Autodesk Inventor part; units mm, degrees
(part 3 of 3)
sketch "Sketch15" plane through (0, 7, 0) normal (0, 1, 0) x (1, 0, 0)
  line L0 (95, 122.5) -> (95, 116.5) projected
  line L1 (95, 116.5) -> (92, 116.5) projected
  line L2 (92, 116.5) -> (92, 122.5) projected
  line L3 (92, 122.5) -> (95, 122.5) projected
  line L4 (146.2845, 46) -> (146.2845, 49) projected
  line L5 (146.2845, 49) -> (156.2155, 49) projected
  line L6 (156.2155, 49) -> (156.2155, 46) projected
  line L7 (156.2155, 46) -> (146.2845, 46) projected
  line L8 (100, 124) -> (107.5, 124) projected
  line L9 (107.5, 124) -> (107.5, 121) projected
  line L10 (107.5, 121) -> (100, 121) projected
  line L11 (100, 121) -> (100, 124) projected
  line L12 (95, 53.5) -> (95, 47.5) projected
  line L13 (95, 47.5) -> (92, 47.5) projected
  line L14 (92, 47.5) -> (92, 53.5) projected
  line L15 (92, 53.5) -> (95, 53.5) projected
  line L16 (98.7845, 46) -> (98.7845, 49) projected
  line L17 (98.7845, 49) -> (108.7155, 49) projected
  line L18 (108.7155, 49) -> (108.7155, 46) projected
  line L19 (108.7155, 46) -> (98.7845, 46) projected
  line L20 (155, 121) -> (147.5, 121) projected
  line L21 (147.5, 121) -> (147.5, 124) projected
  line L22 (147.5, 124) -> (155, 124) projected
  line L23 (155, 124) -> (155, 121) projected
  circle A0 centre (265, 165) radius 1.8 projected
  circle A1 centre (245, 165) radius 1.8 projected
  circle A2 centre (239, 32) radius 1.8 projected
  circle A3 centre (224, 32) radius 1.8 projected
  circle A4 centre (381, -156.5) radius 1.5 projected
  circle A5 centre (134.575, -192.5) radius 1.5 projected
  circle A6 centre (10.325, -226.5) radius 1.5 projected
  line L24 (-299.5, -198) -> (0.5, -198) projected
  arc A7 (0.5, -213) -> (0.5, -198) centre (0.5, -205.5) ccw projected
  line L25 (0.5, -213) -> (-299.5, -213) projected
  arc A8 (-299.5, -198) -> (-299.5, -213) centre (-299.5, -205.5) ccw projected
  circle A9 centre (-123.175, -236) radius 1.65 projected
  line L26 (-282.4, -241.875) -> (-278.4, -241.875) projected
  arc A10 (-278.4, -244.125) -> (-278.4, -241.875) centre (-278.4, -243) ccw projected
  line L27 (-278.4, -244.125) -> (-282.4, -244.125) projected
  arc A11 (-282.4, -241.875) -> (-282.4, -244.125) centre (-282.4, -243) ccw projected
  arc A12 (-157.3, -244.125) -> (-157.3, -241.875) centre (-157.3, -243) ccw projected
  line L28 (-157.3, -244.125) -> (-161.3, -244.125) projected
  arc A13 (-161.3, -241.875) -> (-161.3, -244.125) centre (-161.3, -243) ccw projected
  line L29 (-161.3, -241.875) -> (-157.3, -241.875) projected
  circle A14 centre (-86.175, -236) radius 1.65 projected
  circle A15 centre (-59.675, -226.5) radius 1.5 projected
  circle A16 centre (43.075, -192.5) radius 1.5 projected
  circle A17 centre (381, -212.5) radius 1.5 projected
  circle A18 centre (311, -212.5) radius 1.5 projected
  line L30 (224.5, -222.5) -> (224.5, -252.5) projected
  arc A19 (184.5, -252.5) -> (224.5, -252.5) centre (204.5, -252.5) ccw projected
  line L31 (184.5, -252.5) -> (184.5, -222.5) projected
  arc A20 (224.5, -222.5) -> (184.5, -222.5) centre (204.5, -222.5) ccw projected
  circle A21 centre (134.575, -282.5) radius 1.5 projected
  circle A22 centre (10.325, -282.5) radius 1.5 projected
  circle A23 centre (-123.175, -273) radius 1.65 projected
  line L32 (-373.5, -240.25) -> (-369.5, -240.25) projected
  arc A24 (-369.5, -245.75) -> (-369.5, -240.25) centre (-369.5, -243) ccw projected
  line L33 (-369.5, -245.75) -> (-373.5, -245.75) projected
  arc A25 (-373.5, -240.25) -> (-373.5, -245.75) centre (-373.5, -243) ccw projected
  arc A26 (-252.4, -241.875) -> (-252.4, -244.125) centre (-252.4, -243) ccw projected
  line L34 (-252.4, -241.875) -> (-248.4, -241.875) projected
  arc A27 (-248.4, -244.125) -> (-248.4, -241.875) centre (-248.4, -243) ccw projected
  line L35 (-248.4, -244.125) -> (-252.4, -244.125) projected
  circle A28 centre (-86.175, -273) radius 1.65 projected
  circle A29 centre (-59.675, -282.5) radius 1.5 projected
  circle A30 centre (43.075, -282.5) radius 1.5 projected
  line L36 (332.5, -232) -> (362.5, -232) projected
  arc A31 (362.5, -262) -> (362.5, -232) centre (362.5, -247) ccw projected
  line L37 (362.5, -262) -> (332.5, -262) projected
  arc A32 (332.5, -232) -> (332.5, -262) centre (332.5, -247) ccw projected
  circle A33 centre (311, -156.5) radius 1.5 projected
  circle A34 centre (185.5, -321.5) radius 1 projected
  circle A35 centre (185.5, -79.5) radius 1 projected
  circle A36 centre (0, 184.5) radius 1 projected
  circle A37 centre (-335.5, 184.5) radius 1 projected
  circle A38 centre (-185.5, 321.5) radius 1 projected
  circle A39 centre (-424, -80) radius 1 projected
  circle A40 centre (-424, 80) radius 1 projected
  circle A41 centre (0, 321.5) radius 1 projected
  circle A42 centre (-185.5, 184.5) radius 1 projected
  circle A43 centre (-185.5, -79.5) radius 1 projected
  circle A44 centre (0, -79.5) radius 1 projected
  circle A45 centre (-185.5, -321.5) radius 1 projected
  circle A46 centre (335.5, -321.5) radius 1 projected
  circle A47 centre (335.5, -79.5) radius 1 projected
  circle A48 centre (185.5, 184.5) radius 1 projected
  circle A49 centre (335.5, 321.5) radius 1 projected
  circle A50 centre (-335.5, 321.5) radius 1 projected
  circle A51 centre (-424, -240) radius 1 projected
  circle A52 centre (-424, 240) radius 1 projected
  circle A53 centre (185.5, 321.5) radius 1 projected
  circle A54 centre (335.5, 184.5) radius 1 projected
  circle A55 centre (-335.5, -79.5) radius 1 projected
  circle A56 centre (0, -321.5) radius 1 projected
  circle A57 centre (-335.5, -321.5) radius 1 projected
  arc A58 (-442.5, -333) -> (-435.5, -340) centre (-435.5, -333) ccw projected
  line L38 (-435.5, -340) -> (-383.5, -340) projected
  line L39 (-383.5, -340) -> (-383.5, -333) projected
  line L40 (-383.5, -333) -> (-324.5, -333) projected
  line L41 (-324.5, -333) -> (-324.5, -340) projected
  line L42 (-324.5, -340) -> (-265.5, -340) projected
  line L43 (-265.5, -340) -> (-265.5, -333) projected
  line L44 (-265.5, -333) -> (-206.5, -333) projected
  line L45 (-206.5, -333) -> (-206.5, -340) projected
  line L46 (-206.5, -340) -> (-147.5, -340) projected
  line L47 (-147.5, -340) -> (-147.5, -333) projected
  line L48 (-147.5, -333) -> (-88.5, -333) projected
  line L49 (-88.5, -333) -> (-88.5, -340) projected
  line L50 (-88.5, -340) -> (-29.5, -340) projected
  line L51 (-29.5, -340) -> (-29.5, -333) projected
  line L52 (-29.5, -333) -> (29.5, -333) projected
  line L53 (29.5, -333) -> (29.5, -340) projected
  line L54 (29.5, -340) -> (88.5, -340) projected
  line L55 (88.5, -340) -> (88.5, -333) projected
  line L56 (88.5, -333) -> (147.5, -333) projected
  line L57 (147.5, -333) -> (147.5, -340) projected
  line L58 (147.5, -340) -> (206.5, -340) projected
  line L59 (206.5, -340) -> (206.5, -333) projected
  line L60 (206.5, -333) -> (265.5, -333) projected
  line L61 (265.5, -333) -> (265.5, -340) projected
  line L62 (265.5, -340) -> (324.5, -340) projected
  line L63 (324.5, -340) -> (324.5, -333) projected
  line L64 (324.5, -333) -> (383.5, -333) projected
  line L65 (383.5, -333) -> (383.5, -340) projected
  line L66 (383.5, -340) -> (435.5, -340) projected
  arc A59 (435.5, -340) -> (442.5, -333) centre (435.5, -333) ccw projected
  line L67 (442.5, -333) -> (442.5, -300) projected
  line L68 (442.5, -300) -> (435.5, -300) projected
  line L69 (435.5, -300) -> (435.5, -260) projected
  line L70 (435.5, -260) -> (442.5, -260) projected
  line L71 (442.5, -260) -> (442.5, -220) projected
  line L72 (442.5, -220) -> (435.5, -220) projected
  line L73 (435.5, -220) -> (435.5, -180) projected
  line L74 (435.5, -180) -> (442.5, -180) projected
  line L75 (442.5, -180) -> (442.5, -140) projected
  line L76 (442.5, -140) -> (435.5, -140) projected
  line L77 (435.5, -140) -> (435.5, -100) projected
  line L78 (435.5, -100) -> (442.5, -100) projected
  line L79 (442.5, -100) -> (442.5, -60) projected
  line L80 (442.5, -60) -> (435.5, -60) projected
  line L81 (435.5, -60) -> (435.5, -20) projected
  line L82 (435.5, -20) -> (442.5, -20) projected
  line L83 (442.5, -20) -> (442.5, 20) projected
  line L84 (442.5, 20) -> (435.5, 20) projected
  line L85 (435.5, 20) -> (435.5, 60) projected
  line L86 (435.5, 60) -> (442.5, 60) projected
  line L87 (442.5, 60) -> (442.5, 100) projected
  line L88 (442.5, 100) -> (435.5, 100) projected
  line L89 (435.5, 100) -> (435.5, 140) projected
  line L90 (435.5, 140) -> (442.5, 140) projected
  line L91 (442.5, 140) -> (442.5, 180) projected
  line L92 (442.5, 180) -> (435.5, 180) projected
  line L93 (435.5, 180) -> (435.5, 220) projected
  line L94 (435.5, 220) -> (442.5, 220) projected
  line L95 (442.5, 220) -> (442.5, 260) projected
  line L96 (442.5, 260) -> (435.5, 260) projected
  line L97 (435.5, 260) -> (435.5, 300) projected
  line L98 (435.5, 300) -> (442.5, 300) projected
  line L99 (442.5, 300) -> (442.5, 333) projected
  arc A60 (442.5, 333) -> (435.5, 340) centre (435.5, 333) ccw projected
  line L100 (435.5, 340) -> (383.5, 340) projected
  line L101 (383.5, 340) -> (383.5, 333) projected
  line L102 (383.5, 333) -> (324.5, 333) projected
  line L103 (324.5, 333) -> (324.5, 340) projected
  line L104 (324.5, 340) -> (265.5, 340) projected
  line L105 (265.5, 340) -> (265.5, 333) projected
  line L106 (265.5, 333) -> (206.5, 333) projected
  line L107 (206.5, 333) -> (206.5, 340) projected
  line L108 (206.5, 340) -> (147.5, 340) projected
  line L109 (147.5, 340) -> (147.5, 333) projected
  line L110 (147.5, 333) -> (88.5, 333) projected
  line L111 (88.5, 333) -> (88.5, 340) projected
  line L112 (88.5, 340) -> (29.5, 340) projected
  line L113 (29.5, 340) -> (29.5, 333) projected
  line L114 (29.5, 333) -> (-29.5, 333) projected
  line L115 (-29.5, 333) -> (-29.5, 340) projected
  line L116 (-29.5, 340) -> (-88.5, 340) projected
  line L117 (-88.5, 340) -> (-88.5, 333) projected
  line L118 (-88.5, 333) -> (-147.5, 333) projected
  line L119 (-147.5, 333) -> (-147.5, 340) projected
  line L120 (-147.5, 340) -> (-206.5, 340) projected
  line L121 (-206.5, 340) -> (-206.5, 333) projected
  line L122 (-206.5, 333) -> (-265.5, 333) projected
  line L123 (-265.5, 333) -> (-265.5, 340) projected
  line L124 (-265.5, 340) -> (-324.5, 340) projected
  line L125 (-324.5, 340) -> (-324.5, 333) projected
  line L126 (-324.5, 333) -> (-383.5, 333) projected
  line L127 (-383.5, 333) -> (-383.5, 340) projected
  line L128 (-383.5, 340) -> (-435.5, 340) projected
  arc A61 (-435.5, 340) -> (-442.5, 333) centre (-435.5, 333) ccw projected
  line L129 (-442.5, 333) -> (-442.5, 300) projected
  line L130 (-442.5, 300) -> (-435.5, 300) projected
  line L131 (-435.5, 300) -> (-435.5, 260) projected
  line L132 (-435.5, 260) -> (-442.5, 260) projected
  line L133 (-442.5, 260) -> (-442.5, 220) projected
  line L134 (-442.5, 220) -> (-435.5, 220) projected
  line L135 (-435.5, 220) -> (-435.5, 180) projected
  line L136 (-435.5, 180) -> (-442.5, 180) projected
  line L137 (-442.5, 180) -> (-442.5, 140) projected
  line L138 (-442.5, 140) -> (-435.5, 140) projected
  line L139 (-435.5, 140) -> (-435.5, 100) projected
  line L140 (-435.5, 100) -> (-442.5, 100) projected
  line L141 (-442.5, 100) -> (-442.5, 60) projected
  line L142 (-442.5, 60) -> (-435.5, 60) projected
  line L143 (-435.5, 60) -> (-435.5, 20) projected
  line L144 (-435.5, 20) -> (-442.5, 20) projected
  line L145 (-442.5, 20) -> (-442.5, -20) projected
  line L146 (-442.5, -20) -> (-435.5, -20) projected
  line L147 (-435.5, -20) -> (-435.5, -60) projected
  line L148 (-435.5, -60) -> (-442.5, -60) projected
  line L149 (-442.5, -60) -> (-442.5, -100) projected
  line L150 (-442.5, -100) -> (-435.5, -100) projected
  line L151 (-435.5, -100) -> (-435.5, -140) projected
  line L152 (-435.5, -140) -> (-442.5, -140) projected
  line L153 (-442.5, -140) -> (-442.5, -180) projected
  line L154 (-442.5, -180) -> (-435.5, -180) projected
  line L155 (-435.5, -180) -> (-435.5, -220) projected
  line L156 (-435.5, -220) -> (-442.5, -220) projected
  line L157 (-442.5, -220) -> (-442.5, -260) projected
  line L158 (-442.5, -260) -> (-435.5, -260) projected
  line L159 (-435.5, -260) -> (-435.5, -300) projected
  line L160 (-435.5, -300) -> (-442.5, -300) projected
  line L161 (-442.5, -300) -> (-442.5, -333) projected
  line L162 (97.5, -297) -> (97.5, -300) projected
  line L163 (97.5, -300) -> (-242.5, -300) projected
  line L164 (-242.5, -300) -> (-242.5, -297) projected
  line L165 (-242.5, -297) -> (97.5, -297) projected
  arc A62 (-388, -282.9) -> (-388, -277.1) centre (-388, -280) ccw projected
  line L166 (-388, -282.9) -> (-391, -282.9) projected
  arc A63 (-391, -277.1) -> (-391, -282.9) centre (-391, -280) ccw projected
  line L167 (-391, -277.1) -> (-388, -277.1) projected
  line L168 (211.6, -288.5) -> (211.6, -285.5) projected
  arc A64 (217.4, -285.5) -> (211.6, -285.5) centre (214.5, -285.5) ccw projected
  line L169 (217.4, -285.5) -> (217.4, -288.5) projected
  arc A65 (211.6, -288.5) -> (217.4, -288.5) centre (214.5, -288.5) ccw projected
  line L170 (383, -259.1) -> (386, -259.1) projected
  arc A66 (386, -264.9) -> (386, -259.1) centre (386, -262) ccw projected
  line L171 (386, -264.9) -> (383, -264.9) projected
  arc A67 (383, -259.1) -> (383, -264.9) centre (383, -262) ccw projected
  line L172 (297.5, -150) -> (300.5, -150) projected
  line L173 (300.5, -150) -> (300.5, -250) projected
  line L174 (300.5, -250) -> (297.5, -250) projected
  line L175 (297.5, -250) -> (297.5, -150) projected
  arc A68 (376.6, -114.5) -> (382.4, -114.5) centre (379.5, -114.5) ccw projected
  line L176 (376.6, -114.5) -> (376.6, -111.5) projected
  arc A69 (382.4, -111.5) -> (376.6, -111.5) centre (379.5, -111.5) ccw projected
  line L177 (382.4, -111.5) -> (382.4, -114.5) projected
  line L178 (372.5, -100) -> (372.5, -103) projected
  line L179 (372.5, -103) -> (322.5, -103) projected
  line L180 (322.5, -103) -> (322.5, -100) projected
  line L181 (322.5, -100) -> (372.5, -100) projected
  line L182 (394.5, -150) -> (397.5, -150) projected
  line L183 (397.5, -150) -> (397.5, -250) projected
  line L184 (397.5, -250) -> (394.5, -250) projected
  line L185 (394.5, -250) -> (394.5, -150) projected
  line L186 (382.4, -285.5) -> (382.4, -288.5) projected
  arc A70 (376.6, -288.5) -> (382.4, -288.5) centre (379.5, -288.5) ccw projected
  line L187 (376.6, -288.5) -> (376.6, -285.5) projected
  arc A71 (382.4, -285.5) -> (376.6, -285.5) centre (379.5, -285.5) ccw projected
  arc A72 (211.6, -189.5) -> (217.4, -189.5) centre (214.5, -189.5) ccw projected
  line L188 (211.6, -189.5) -> (211.6, -186.5) projected
  arc A73 (217.4, -186.5) -> (211.6, -186.5) centre (214.5, -186.5) ccw projected
  line L189 (217.4, -186.5) -> (217.4, -189.5) projected
  arc A74 (-391, -192.1) -> (-391, -197.9) centre (-391, -195) ccw projected
  line L190 (-391, -192.1) -> (-388, -192.1) projected
  arc A75 (-388, -197.9) -> (-388, -192.1) centre (-388, -195) ccw projected
  line L191 (-388, -197.9) -> (-391, -197.9) projected
  line L192 (-242.5, -178) -> (-242.5, -175) projected
  line L193 (-242.5, -175) -> (97.5, -175) projected
  line L194 (97.5, -175) -> (97.5, -178) projected
  line L195 (97.5, -178) -> (-242.5, -178) projected
  line L196 (-399.5, -287.5) -> (-402.5, -287.5) projected
  line L197 (-402.5, -287.5) -> (-402.5, -187.5) projected
  line L198 (-402.5, -187.5) -> (-399.5, -187.5) projected
  line L199 (-399.5, -187.5) -> (-399.5, -287.5) projected
  arc A76 (-356.6, -285.5) -> (-362.4, -285.5) centre (-359.5, -285.5) ccw projected
  line L200 (-356.6, -285.5) -> (-356.6, -288.5) projected
  arc A77 (-362.4, -288.5) -> (-356.6, -288.5) centre (-359.5, -288.5) ccw projected
  line L201 (-362.4, -288.5) -> (-362.4, -285.5) projected
  line L202 (243, -277.1) -> (246, -277.1) projected
  arc A78 (246, -282.9) -> (246, -277.1) centre (246, -280) ccw projected
  line L203 (246, -282.9) -> (243, -282.9) projected
  arc A79 (243, -277.1) -> (243, -282.9) centre (243, -280) ccw projected
  arc A80 (318.4, -285.5) -> (312.6, -285.5) centre (315.5, -285.5) ccw projected
  line L204 (318.4, -285.5) -> (318.4, -288.5) projected
  arc A81 (312.6, -288.5) -> (318.4, -288.5) centre (315.5, -288.5) ccw projected
  line L205 (312.6, -288.5) -> (312.6, -285.5) projected
  line L206 (318.4, -111.5) -> (318.4, -114.5) projected
  arc A82 (312.6, -114.5) -> (318.4, -114.5) centre (315.5, -114.5) ccw projected
  line L207 (312.6, -114.5) -> (312.6, -111.5) projected
  arc A83 (318.4, -111.5) -> (312.6, -111.5) centre (315.5, -111.5) ccw projected
  arc A84 (386, -140.9) -> (386, -135.1) centre (386, -138) ccw projected
  line L208 (386, -140.9) -> (383, -140.9) projected
  arc A85 (383, -135.1) -> (383, -140.9) centre (383, -138) ccw projected
  line L209 (383, -135.1) -> (386, -135.1) projected
  line L210 (309, -135.1) -> (312, -135.1) projected
  arc A86 (312, -140.9) -> (312, -135.1) centre (312, -138) ccw projected
  line L211 (312, -140.9) -> (309, -140.9) projected
  arc A87 (309, -135.1) -> (309, -140.9) centre (309, -138) ccw projected
  arc A88 (309, -259.1) -> (309, -264.9) centre (309, -262) ccw projected
  line L212 (309, -259.1) -> (312, -259.1) projected
  arc A89 (312, -264.9) -> (312, -259.1) centre (312, -262) ccw projected
  line L213 (312, -264.9) -> (309, -264.9) projected
  line L214 (322.5, -300) -> (322.5, -297) projected
  line L215 (322.5, -297) -> (372.5, -297) projected
  line L216 (372.5, -297) -> (372.5, -300) projected
  line L217 (372.5, -300) -> (322.5, -300) projected
  arc A90 (246, -197.9) -> (246, -192.1) centre (246, -195) ccw projected
  line L218 (246, -197.9) -> (243, -197.9) projected
  arc A91 (243, -192.1) -> (243, -197.9) centre (243, -195) ccw projected
  line L219 (243, -192.1) -> (246, -192.1) projected
  line L220 (-362.4, -189.5) -> (-362.4, -186.5) projected
  arc A92 (-356.6, -186.5) -> (-362.4, -186.5) centre (-359.5, -186.5) ccw projected
  line L221 (-356.6, -186.5) -> (-356.6, -189.5) projected
  arc A93 (-362.4, -189.5) -> (-356.6, -189.5) centre (-359.5, -189.5) ccw projected
  line L222 (254.5, -187.5) -> (257.5, -187.5) projected
  line L223 (257.5, -187.5) -> (257.5, -287.5) projected
  line L224 (257.5, -287.5) -> (254.5, -287.5) projected
  line L225 (254.5, -287.5) -> (254.5, -187.5) projected
  line L226 (202.5, 101) -> (355.1, 101) projected
  arc A94 (358.1, 98) -> (355.1, 101) centre (355.1, 98) ccw projected
  line L227 (358.1, 98) -> (358.1, 72) projected
  arc A95 (355.1, 69) -> (358.1, 72) centre (355.1, 72) ccw projected
  line L228 (355.1, 69) -> (202.5, 69) projected
  arc A96 (199.5, 72) -> (202.5, 69) centre (202.5, 72) ccw projected
  line L229 (199.5, 72) -> (199.5, 98) projected
  arc A97 (202.5, 101) -> (199.5, 98) centre (202.5, 98) ccw projected
  circle A98 centre (375.1, 69) radius 2.9 projected
  circle A99 centre (375.1, 101) radius 2.9 projected
  circle A100 centre (182.5, 69) radius 2.9 projected
  circle A101 centre (182.5, 101) radius 2.9 projected
  arc A102 (200.9, 198.5) -> (195.1, 198.5) centre (198, 198.5) ccw projected
  line L230 (200.9, 198.5) -> (200.9, 195.5) projected
  arc A103 (195.1, 195.5) -> (200.9, 195.5) centre (198, 195.5) ccw projected
  line L231 (195.1, 195.5) -> (195.1, 198.5) projected
  line L232 (357, 193.5) -> (360, 193.5) projected
  line L233 (360, 193.5) -> (360, 173.5) projected
  line L234 (360, 173.5) -> (357, 173.5) projected
  line L235 (357, 173.5) -> (357, 193.5) projected
  line L236 (357, -3.5) -> (360, -3.5) projected
  line L237 (360, -3.5) -> (360, -23.5) projected
  line L238 (360, -23.5) -> (357, -23.5) projected
  line L239 (357, -23.5) -> (357, -3.5) projected
  line L240 (163, -23.5) -> (160, -23.5) projected
  line L241 (160, -23.5) -> (160, -3.5) projected
  line L242 (160, -3.5) -> (163, -3.5) projected
  line L243 (163, -3.5) -> (163, -23.5) projected
  arc A104 (345.5, -10.6) -> (345.5, -16.4) centre (345.5, -13.5) ccw projected
  line L244 (345.5, -10.6) -> (348.5, -10.6) projected
  arc A105 (348.5, -16.4) -> (348.5, -10.6) centre (348.5, -13.5) ccw projected
  line L245 (348.5, -16.4) -> (345.5, -16.4) projected
  line L246 (348.5, 180.6) -> (345.5, 180.6) projected
  arc A106 (345.5, 186.4) -> (345.5, 180.6) centre (345.5, 183.5) ccw projected
  line L247 (345.5, 186.4) -> (348.5, 186.4) projected
  arc A107 (348.5, 180.6) -> (348.5, 186.4) centre (348.5, 183.5) ccw projected
  arc A108 (174.5, 180.6) -> (174.5, 186.4) centre (174.5, 183.5) ccw projected
  line L248 (174.5, 180.6) -> (171.5, 180.6) projected
  arc A109 (171.5, 186.4) -> (171.5, 180.6) centre (171.5, 183.5) ccw projected
  line L249 (171.5, 186.4) -> (174.5, 186.4) projected
  line L250 (332.5, 210) -> (332.5, 207) projected
  line L251 (332.5, 207) -> (187.5, 207) projected
  line L252 (187.5, 207) -> (187.5, 210) projected
  line L253 (187.5, 210) -> (332.5, 210) projected
  arc A110 (324.9, -25.5) -> (319.1, -25.5) centre (322, -25.5) ccw projected
  line L254 (324.9, -25.5) -> (324.9, -28.5) projected
  arc A111 (319.1, -28.5) -> (324.9, -28.5) centre (322, -28.5) ccw projected
  line L255 (319.1, -28.5) -> (319.1, -25.5) projected
  line L256 (200.9, -25.5) -> (200.9, -28.5) projected
  arc A112 (195.1, -28.5) -> (200.9, -28.5) centre (198, -28.5) ccw projected
  line L257 (195.1, -28.5) -> (195.1, -25.5) projected
  arc A113 (200.9, -25.5) -> (195.1, -25.5) centre (198, -25.5) ccw projected
  line L258 (174.5, -16.4) -> (171.5, -16.4) projected
  arc A114 (171.5, -10.6) -> (171.5, -16.4) centre (171.5, -13.5) ccw projected
  line L259 (171.5, -10.6) -> (174.5, -10.6) projected
  arc A115 (174.5, -16.4) -> (174.5, -10.6) centre (174.5, -13.5) ccw projected
  line L260 (187.5, -40) -> (187.5, -37) projected
  line L261 (187.5, -37) -> (332.5, -37) projected
  line L262 (332.5, -37) -> (332.5, -40) projected
  line L263 (332.5, -40) -> (187.5, -40) projected
  line L264 (324.9, 198.5) -> (324.9, 195.5) projected
  arc A116 (319.1, 195.5) -> (324.9, 195.5) centre (322, 195.5) ccw projected
  line L265 (319.1, 195.5) -> (319.1, 198.5) projected
  arc A117 (324.9, 198.5) -> (319.1, 198.5) centre (322, 198.5) ccw projected
  line L266 (160, 193.5) -> (163, 193.5) projected
  line L267 (163, 193.5) -> (163, 173.5) projected
  line L268 (163, 173.5) -> (160, 173.5) projected
  line L269 (160, 173.5) -> (160, 193.5) projected
  line L270 (95.5, -49.5) -> (95.5, -34.5) projected
  line L271 (95.5, -34.5) -> (98.5, -34.5) projected
  line L272 (98.5, -34.5) -> (98.5, -49.5) projected
  line L273 (98.5, -49.5) -> (95.5, -49.5) projected
  arc A118 (135.5, -40) -> (140.5, -35) centre (135.5, -35) ccw projected
  line L274 (135.5, -40) -> (115.5, -40) projected
  arc A119 (110.5, -35) -> (115.5, -40) centre (115.5, -35) ccw projected
  line L275 (110.5, -35) -> (110.5, -25) projected
  arc A120 (115.5, -20) -> (110.5, -25) centre (115.5, -25) ccw projected
  line L276 (115.5, -20) -> (135.5, -20) projected
  arc A121 (140.5, -25) -> (135.5, -20) centre (135.5, -25) ccw projected
  line L277 (140.5, -25) -> (140.5, -35) projected
  line L278 (103.25, 40) -> (113.25, 40) projected
  line L279 (113.25, 40) -> (113.25, 37) projected
  line L280 (113.25, 37) -> (103.25, 37) projected
  line L281 (103.25, 37) -> (103.25, 40) projected
  line L282 (113, 130) -> (108, 130) projected
  line L283 (108, 130) -> (108, 133) projected
  line L284 (108, 133) -> (113, 133) projected
  line L285 (113, 133) -> (113, 130) projected
  line L286 (149, 130) -> (144, 130) projected
  line L287 (144, 130) -> (144, 133) projected
  line L288 (144, 133) -> (149, 133) projected
  line L289 (149, 133) -> (149, 130) projected
  circle A122 centre (132.41, 31.5) radius 1.25 projected
  line L290 (156.5, 138) -> (153.5, 138) projected
  line L291 (153.5, 138) -> (153.5, 148) projected
  line L292 (153.5, 148) -> (156.5, 148) projected
  line L293 (156.5, 148) -> (156.5, 138) projected
  line L294 (108, 156) -> (113, 156) projected
  line L295 (113, 156) -> (113, 153) projected
  line L296 (113, 153) -> (108, 153) projected
  line L297 (108, 153) -> (108, 156) projected
  line L298 (95.5, 14.5) -> (95.5, 29.5) projected
  line L299 (95.5, 29.5) -> (98.5, 29.5) projected
  line L300 (98.5, 29.5) -> (98.5, 14.5) projected
  line L301 (98.5, 14.5) -> (95.5, 14.5) projected
  line L302 (113.25, 4) -> (103.25, 4) projected
  line L303 (103.25, 4) -> (103.25, 7) projected
  line L304 (103.25, 7) -> (113.25, 7) projected
  line L305 (113.25, 7) -> (113.25, 4) projected
  line L306 (113.25, -60) -> (103.25, -60) projected
  line L307 (103.25, -60) -> (103.25, -57) projected
  line L308 (103.25, -57) -> (113.25, -57) projected
  line L309 (113.25, -57) -> (113.25, -60) projected
  line L310 (51.5, 95) -> (51.5, 75) projected
  line L311 (51.5, 75) -> (44.5, 75) projected
  line L312 (44.5, 75) -> (44.5, 95) projected
  line L313 (44.5, 95) -> (51.5, 95) projected
  line L314 (155.5, -34.5) -> (155.5, -49.5) projected
  line L315 (155.5, -49.5) -> (152.5, -49.5) projected
  line L316 (152.5, -49.5) -> (152.5, -34.5) projected
  line L317 (152.5, -34.5) -> (155.5, -34.5) projected
  line L318 (137.75, 40) -> (147.75, 40) projected
  line L319 (147.75, 40) -> (147.75, 37) projected
  line L320 (147.75, 37) -> (137.75, 37) projected
  line L321 (137.75, 37) -> (137.75, 40) projected
  line L322 (100.5, 138) -> (100.5, 148) projected
  line L323 (100.5, 148) -> (103.5, 148) projected
  line L324 (103.5, 148) -> (103.5, 138) projected
  line L325 (103.5, 138) -> (100.5, 138) projected
  line L326 (134.5, 139) -> (122.5, 139) projected
  arc A123 (122.5, 147) -> (122.5, 139) centre (122.5, 143) ccw projected
  line L327 (122.5, 147) -> (134.5, 147) projected
  arc A124 (134.5, 139) -> (134.5, 147) centre (134.5, 143) ccw projected
  circle A125 centre (118.59, 31.5) radius 1.25 projected
  line L328 (144, 156) -> (149, 156) projected
  line L329 (149, 156) -> (149, 153) projected
  line L330 (149, 153) -> (144, 153) projected
  line L331 (144, 153) -> (144, 156) projected
  line L332 (126.5, 136) -> (130.5, 136) projected
  line L333 (130.5, 136) -> (130.5, 133) projected
  line L334 (130.5, 133) -> (126.5, 133) projected
  line L335 (126.5, 133) -> (126.5, 136) projected
  line L336 (155.5, 29.5) -> (155.5, 14.5) projected
  line L337 (155.5, 14.5) -> (152.5, 14.5) projected
  line L338 (152.5, 14.5) -> (152.5, 29.5) projected
  line L339 (152.5, 29.5) -> (155.5, 29.5) projected
  line L340 (137.75, 4) -> (137.75, 7) projected
  line L341 (137.75, 7) -> (147.75, 7) projected
  line L342 (147.75, 7) -> (147.75, 4) projected
  line L343 (147.75, 4) -> (137.75, 4) projected
  line L344 (147.75, -60) -> (137.75, -60) projected
  line L345 (137.75, -60) -> (137.75, -57) projected
  line L346 (137.75, -57) -> (147.75, -57) projected
  line L347 (147.75, -57) -> (147.75, -60) projected
  line L348 (42.5, 92.5) -> (42.5, 77.5) projected
  line L349 (42.5, 77.5) -> (39.5, 77.5) projected
  line L350 (39.5, 77.5) -> (39.5, 92.5) projected
  line L351 (39.5, 92.5) -> (42.5, 92.5) projected
  circle A126 centre (32.5, 114.5) radius 2.75 projected
  circle A127 centre (32.5, 55.5) radius 2.75 projected
  circle A128 centre (-112.5, 155) radius 2.75 projected
  circle A129 centre (-47.5, 15) radius 2.75 projected
  circle A130 centre (-112.5, 15) radius 2.75 projected
  circle A131 centre (-47.5, 155) radius 2.75 projected
  circle A132 centre (-177.5, 155) radius 2.75 projected
  circle A133 centre (-177.5, 15) radius 2.75 projected
  line L352 (-407.5, 305) -> (-387.5, 305) projected
  line L353 (-387.5, 305) -> (-387.5, 285) projected
  line L354 (-387.5, 285) -> (-407.5, 285) projected
  line L355 (-407.5, 285) -> (-407.5, 305) projected
  arc A134 (-419, -122.1) -> (-419, -127.9) centre (-419, -125) ccw projected
  line L356 (-419, -122.1) -> (-416, -122.1) projected
  arc A135 (-416, -127.9) -> (-416, -122.1) centre (-416, -125) ccw projected
  line L357 (-416, -127.9) -> (-419, -127.9) projected
  arc A136 (100.4, -143.5) -> (94.6, -143.5) centre (97.5, -143.5) ccw projected
  line L358 (100.4, -143.5) -> (100.4, -146.5) projected
  arc A137 (94.6, -146.5) -> (100.4, -146.5) centre (97.5, -146.5) ccw projected
  line L359 (94.6, -146.5) -> (94.6, -143.5) projected
  line L360 (107.5, -115) -> (107.5, -135) projected
  line L361 (107.5, -135) -> (87.5, -135) projected
  line L362 (87.5, -135) -> (87.5, -115) projected
  line L363 (87.5, -115) -> (107.5, -115) projected
  arc A138 (100.4, 316.5) -> (94.6, 316.5) centre (97.5, 316.5) ccw projected
  line L364 (100.4, 316.5) -> (100.4, 313.5) projected
  arc A139 (94.6, 313.5) -> (100.4, 313.5) centre (97.5, 313.5) ccw projected
  line L365 (94.6, 313.5) -> (94.6, 316.5) projected
  arc A140 (76, 297.9) -> (76, 292.1) centre (76, 295) ccw projected
  line L366 (76, 297.9) -> (79, 297.9) projected
  arc A141 (79, 292.1) -> (79, 297.9) centre (79, 295) ccw projected
  line L367 (79, 292.1) -> (76, 292.1) projected
  arc A142 (116, -122.1) -> (116, -127.9) centre (116, -125) ccw projected
  line L368 (116, -122.1) -> (119, -122.1) projected
  arc A143 (119, -127.9) -> (119, -122.1) centre (119, -125) ccw projected
  line L369 (119, -127.9) -> (116, -127.9) projected
  line L370 (-387.5, -135) -> (-407.5, -135) projected
  line L371 (-407.5, -135) -> (-407.5, -115) projected
  line L372 (-407.5, -115) -> (-387.5, -115) projected
  line L373 (-387.5, -115) -> (-387.5, -135) projected
  arc A144 (-394.6, -143.5) -> (-400.4, -143.5) centre (-397.5, -143.5) ccw projected
  line L374 (-394.6, -143.5) -> (-394.6, -146.5) projected
  arc A145 (-400.4, -146.5) -> (-394.6, -146.5) centre (-397.5, -146.5) ccw projected
  line L375 (-400.4, -146.5) -> (-400.4, -143.5) projected
  arc A146 (-379, 297.9) -> (-379, 292.1) centre (-379, 295) ccw projected
  line L376 (-379, 297.9) -> (-376, 297.9) projected
  arc A147 (-376, 292.1) -> (-376, 297.9) centre (-376, 295) ccw projected
  line L377 (-376, 292.1) -> (-379, 292.1) projected
  arc A148 (-394.6, 276.5) -> (-400.4, 276.5) centre (-397.5, 276.5) ccw projected
  line L378 (-394.6, 276.5) -> (-394.6, 273.5) projected
  arc A149 (-400.4, 273.5) -> (-394.6, 273.5) centre (-397.5, 273.5) ccw projected
  line L379 (-400.4, 273.5) -> (-400.4, 276.5) projected
  arc A150 (-394.6, -103.5) -> (-400.4, -103.5) centre (-397.5, -103.5) ccw projected
  line L380 (-394.6, -103.5) -> (-394.6, -106.5) projected
  arc A151 (-400.4, -106.5) -> (-394.6, -106.5) centre (-397.5, -106.5) ccw projected
  line L381 (-400.4, -106.5) -> (-400.4, -103.5) projected
  arc A152 (76, -122.1) -> (76, -127.9) centre (76, -125) ccw projected
  line L382 (76, -122.1) -> (79, -122.1) projected
  arc A153 (79, -127.9) -> (79, -122.1) centre (79, -125) ccw projected
  line L383 (79, -127.9) -> (76, -127.9) projected
  arc A154 (116, 297.9) -> (116, 292.1) centre (116, 295) ccw projected
  line L384 (116, 297.9) -> (119, 297.9) projected
  arc A155 (119, 292.1) -> (119, 297.9) centre (119, 295) ccw projected
  line L385 (119, 292.1) -> (116, 292.1) projected
  line L386 (107.5, 305) -> (107.5, 285) projected
  line L387 (107.5, 285) -> (87.5, 285) projected
  line L388 (87.5, 285) -> (87.5, 305) projected
  line L389 (87.5, 305) -> (107.5, 305) projected
  arc A156 (100.4, 276.5) -> (94.6, 276.5) centre (97.5, 276.5) ccw projected
  line L390 (100.4, 276.5) -> (100.4, 273.5) projected
  arc A157 (94.6, 273.5) -> (100.4, 273.5) centre (97.5, 273.5) ccw projected
  line L391 (94.6, 273.5) -> (94.6, 276.5) projected
  arc A158 (100.4, -103.5) -> (94.6, -103.5) centre (97.5, -103.5) ccw projected
  line L392 (100.4, -103.5) -> (100.4, -106.5) projected
  arc A159 (94.6, -106.5) -> (100.4, -106.5) centre (97.5, -106.5) ccw projected
  line L393 (94.6, -106.5) -> (94.6, -103.5) projected
  arc A160 (-379, -122.1) -> (-379, -127.9) centre (-379, -125) ccw projected
  line L394 (-379, -122.1) -> (-376, -122.1) projected
  arc A161 (-376, -127.9) -> (-376, -122.1) centre (-376, -125) ccw projected
  line L395 (-376, -127.9) -> (-379, -127.9) projected
  line L396 (-416, 292.1) -> (-419, 292.1) projected
  arc A162 (-419, 297.9) -> (-419, 292.1) centre (-419, 295) ccw projected
  line L397 (-419, 297.9) -> (-416, 297.9) projected
  arc A163 (-416, 292.1) -> (-416, 297.9) centre (-416, 295) ccw projected
  line L398 (-400.4, 313.5) -> (-400.4, 316.5) projected
  arc A164 (-394.6, 316.5) -> (-400.4, 316.5) centre (-397.5, 316.5) ccw projected
  line L399 (-394.6, 316.5) -> (-394.6, 313.5) projected
  arc A165 (-400.4, 313.5) -> (-394.6, 313.5) centre (-397.5, 313.5) ccw projected
  circle A166 centre (410.5, -308) radius 1.5
  circle A167 centre (-410.5, -308) radius 1.5
  circle A168 centre (0, -308) radius 1.5
  circle A169 centre (-417.5, 0) radius 1.5
  circle A170 centre (417.5, 0) radius 1.5
  circle A171 centre (0, 0) radius 1.5
  circle A172 centre (410.5, 308) radius 1.5
  circle A173 centre (0, 308) radius 1.5
  circle A174 centre (-295, 308) radius 1.5
  circle A175 centre (-410.5, 200) radius 1.5
  point P0 (0, -333)
  point P1 (-442.5, 0)
  point P2 (442.5, 0)
  point P3 (0, 333)
  point P4 (-295, 340)
  point P5 (-435.5, 200)
  dimension "d414" = 3
  dimension "d416" = 25
  dimension "d417" = 25
  dimension "d418" = 3
  dimension "d419" = 25
  dimension "d420" = 25
  dimension "d421" = 3
  dimension "d422" = 25
  dimension "d423" = 3
  dimension "d424" = 25
  dimension "d425" = 3
  dimension "d426" = 25
  dimension "d427" = 3
  dimension "d428" = 3
  dimension "d429" = 25
  dimension "d430" = 25
  dimension "d431" = 3
  dimension "d432" = 25
  dimension "d433" = 3
  dimension "d434" = 25
  dimension "d435" = 3
  dimension "d436" = 25
  constraints: 10 centre point, 6 midpoint, 3 horizontal alignment, 3 vertical alignment, 1 coincident
  measures "d414" diameter of A166
  measures "d416" distance from line of L69 A166.centre
  measures "d417" distance from line of A166.centre L64
  measures "d418" diameter of A167
  measures "d419" distance from line of L159 A167.centre
  measures "d420" distance from line of L40 A167.centre
  measures "d421" diameter of A168
  measures "d422" distance from line of L52 A168.centre
  measures "d423" diameter of A169
  measures "d424" distance from line of L145 A169.centre
  measures "d425" diameter of A170
  measures "d426" distance from line of L83 A170.centre
  measures "d427" diameter of A171
  measures "d428" diameter of A172
  measures "d429" distance from line of A172.centre L102
  measures "d430" distance from line of L97 A172.centre
  measures "d431" diameter of A173
  measures "d432" distance from line of L114 A173.centre
  measures "d433" diameter of A174
  measures "d434" distance from line of L126 A174.centre
  measures "d435" diameter of A175
  measures "d436" distance from line of L135 A175.centre
extrude "Extrusion11" cut sketch "Sketch15" against normal through all contours A166 | A167 | A168 | A169 | A170 | A171 | A172 | A173 | A174 | A175
sketch "Sketch16" plane through (0, 7, 0) normal (0, 1, 0) x (1, 0, 0)
  line L0 (375.1, 58.8393) -> (378.1, 58.8393) construction
  line L1 (375.1, 55.9393) -> (378.1, 55.9393)
  line L2 (378.1, 61.7393) -> (375.1, 61.7393)
  arc A0 (375.1, 61.7393) -> (375.1, 55.9393) centre (375.1, 58.8393) ccw
  arc A1 (378.1, 55.9393) -> (378.1, 61.7393) centre (378.1, 58.8393) ccw
  circle A2 centre (375.1, 69) radius 2.9 projected
  line L3 (375.1, 69) -> (375.1, 58.8393)
  line L4 (199.5, 98) -> (199.5, 72) projected
  line L5 (199.5, 85) -> (358.1, 85) construction
  line L6 (358.1, 72) -> (358.1, 98) projected
  line L7 (375.1, 111.1607) -> (378.1, 111.1607) construction
  line L8 (375.1, 114.0607) -> (378.1, 114.0607)
  line L9 (378.1, 108.2607) -> (375.1, 108.2607)
  arc A3 (375.1, 114.0607) -> (375.1, 108.2607) centre (375.1, 111.1607) ccw
  arc A4 (378.1, 108.2607) -> (378.1, 114.0607) centre (378.1, 111.1607) ccw
  line L10 (202.5, 69) -> (355.1, 69) projected
  line L11 (376.6, 58.8393) -> (216, 58.8393) construction
  line L12 (296.3, 66.3393) -> (296.3, 51.3393) construction
  line L13 (217.5, 58.8393) -> (214.5, 58.8393) construction
  line L14 (217.5, 55.9393) -> (214.5, 55.9393)
  line L15 (214.5, 61.7393) -> (217.5, 61.7393)
  arc A5 (217.5, 55.9393) -> (217.5, 61.7393) centre (217.5, 58.8393) ccw
  arc A6 (214.5, 61.7393) -> (214.5, 55.9393) centre (214.5, 58.8393) ccw
  line L16 (217.5, 111.1607) -> (214.5, 111.1607) construction
  line L17 (217.5, 114.0607) -> (214.5, 114.0607)
  line L18 (214.5, 108.2607) -> (217.5, 108.2607)
  arc A7 (217.5, 108.2607) -> (217.5, 114.0607) centre (217.5, 111.1607) ccw
  arc A8 (214.5, 114.0607) -> (214.5, 108.2607) centre (214.5, 111.1607) ccw
  point P0 (0, 0)
  point P1 (376.6, 111.1607)
  point P2 (296.3, 58.8393)
  point P3 (216, 111.1607)
  dimension "d439" = 5.8
  dimension "d440" = 3
  dimension "d441" = 10.1607
  dimension "d442" = 160.6
  dimension "d443" = 15
  constraints: 40 end point, 20 symmetric about line, 16 point on circle, 8 centre point, 5 midpoint, 4 tangent, 2 horizontal, 2 vertical, 1 parallel, 6 other
  measures "d439" diameter of A1
  measures "d440" distance of L0.start L0.end
  measures "d441" vertical distance of L3.start L11.start
  measures "d442" distance of L11.start L11.end
  measures "d443" distance of L12.start L12.end
extrude "Extrusion12" cut sketch "Sketch16" against normal blind 10 contours A0 L2 A1 L1 | L8 A4 L9 A3 | L14 A6 L15 A5 | A7 L18 A8 L17
equation "\"d0\" = BaseTotalWidth"
equation "\"d1\" = BaseTotalLength"
equation "\"d2\" = BaseWoodThickness"
equation "\"d6\" = AluminiumExtrusionClearance"
equation "\"d7\" = AluminiumExtrusionClearance"
equation "\"d8\" = WorkspaceWidth"
equation "\"d9\" = WorkspaceLength"
equation "\"d10\" = AluminiumExtrusionBase"
equation "\"d11\" = AluminiumExtrusionBase"
equation "\"d20\" = WorkspaceWidth - AluminiumExtrusionBase"
equation "\"d23\" = WorkspaceLength - AluminiumExtrusionBase"
equation "\"d30\" = GridRobotClearance + AluminiumExtrusionBase + GridTotalSize"
equation "\"d33\" = 2 * GridTotalSize + DistanceBetweenGrid"
equation "\"d36\" = GridTotalSize"
equation "\"d47\" = GridTotalSize"
equation "\"d101\" = d145"
equation "\"d188\" = BoxesWidth"
equation "\"d189\" = PowerBoxLength"
equation "\"d191\" = BoxesClearance"
equation "\"d192\" = ContolBoxLength"
equation "\"d193\" = ContolBoxWidth"
equation "\"d194\" = BoxesClearance"
equation "\"d195\" = BoxesClearance"
equation "\"GridProcutClearance\" = 5"
equation "\"GridBorderThickness\" = 5"
equation "\"GridBorderFillets\" = 7"
equation "\"GridTotalSize\" = 65"
equation "\"GridRobotClearance\" = 65"
equation "\"AluminiumExtrusionBase\" = 20"
equation "\"AluminiumExtrusionClearance\" = 35"
equation "\"BaseTotalWidth\" = 680"
equation "\"BaseTotalLength\" = 885"
equation "\"WorkspaceLength\" = 515"
equation "\"WorkspaceWidth\" = 440"
equation "\"WorkspaceHeight\" = 183"
equation "\"AxesBaseFillet\" = 15"
equation "\"Zaxis\" = 197"
equation "\"ProductTotalHeight\" = 45"
equation "\"VerticalStroke\" = 105"
equation "\"BackArea\" = 165"
equation "\"CylinderStroke\" = 75"
equation "\"BoxesClearance\" = 40"
equation "\"BoxesWidth\" = 125"
equation "\"PowerBoxLength\" = 660"
equation "\"ContolBoxLength\" = 100"
equation "\"ContolBoxWidth\" = 200"
equation "\"BaseWoodThickness\" = 7"
equation "\"Kerf\" = 0.3"
equation "\"RxThickness\" = 1.8"
equation "\"support_2\" = 265"
equation "\"DistanceBetweenGrid\" = 10"
equation "\"d145\" = 100"
body "Solid1"
